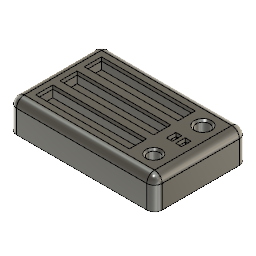
stand_ian270033 (Autodesk Fusion 360 design; units mm, degrees)
Autodesk Fusion 360 part; units mm, degrees
sketch "Sketch1" plane through (0, 0, 0) normal (0, 0, 1) x (1, 0, 0)
  line L0 (0, 0) -> (94.3, 0)
  line L1 (94.3, 0) -> (94.3, 60)
  line L2 (94.3, 60) -> (0, 60)
  line L3 (0, 60) -> (0, 0)
  dimension "d1" = 94.3
  dimension "d2" = 60
  constraint horizontal L0
  constraint vertical L1
  constraint horizontal L2
  constraint vertical L3
  constraint coincident L0.start L3.end
  measures "d1" distance of L0.start L0.end
  measures "d2" distance of L0 L2
extrude "Extrude1" add sketch "Sketch1" along normal blind 20
sketch "Sketch2" plane through (0, 0, 20) normal (0, 0, 1) x (-1, 0, 0)
  line L0 (0, -60) -> (0, 0)
  line L1 (0, 0) -> (-94.3, 0)
  line L2 (-94.3, 0) -> (-94.3, -60)
  line L3 (-94.3, -60) -> (0, -60)
  line L4 (-9.9, -50.1) -> (-68.1, -50.1)
  line L5 (-68.1, -50.1) -> (-68.1, -41.4)
  line L6 (-68.1, -41.4) -> (-9.9, -41.4)
  line L7 (-9.9, -41.4) -> (-9.9, -50.1)
  line L8 (-9.9, -34.35) -> (-68.1, -34.35)
  line L9 (-68.1, -25.65) -> (-9.9, -25.65)
  line L10 (-9.9, -25.65) -> (-9.9, -34.35)
  line L11 (-68.1, -34.35) -> (-68.1, -25.65)
  line L12 (0, 15.75) -> (-94.3, 15.75)
  line L13 (-9.9, -18.6) -> (-68.1, -18.6)
  line L14 (-68.1, -9.9) -> (-9.9, -9.9)
  line L15 (-9.9, -9.9) -> (-9.9, -18.6)
  line L16 (-68.1, -18.6) -> (-68.1, -9.9)
  line L17 (0, 31.5) -> (-94.3, 31.5)
  dimension "d5" = 8.7
  dimension "d6" = 58.2
  dimension "d7" = 9.9
  dimension "d8" = 9.9
  dimension "d11" = 0
  dimension "d12" = 31.5
  constraint horizontal L4
  constraint vertical L5
  constraint horizontal L6
  constraint vertical L7
  measures "d5" distance of L4.start L6.end
  measures "d6" distance of L4.start L4.end
  measures "d7" distance of L0 L7
  measures "d8" distance of L3 L4
extrude "Extrude2" cut sketch "Sketch2" against normal blind 6 contours L4 L5 L6 L7 | L8 L9 L10 L11 | L13 L14 L15 L16
sketch "Sketch3" plane through (0, 0, 20) normal (0, 0, 1) x (-1, 0, 0)
  line L0 (-9.9, -9.9) -> (-9.9, -18.6)
  line L1 (-9.9, -18.6) -> (-68.1, -18.6)
  line L2 (-68.1, -18.6) -> (-68.1, -9.9)
  line L3 (-68.1, -9.9) -> (-9.9, -9.9)
  line L4 (-9.9, -25.65) -> (-9.9, -34.35)
  line L5 (-9.9, -34.35) -> (-68.1, -34.35)
  line L6 (-68.1, -34.35) -> (-68.1, -25.65)
  line L7 (-68.1, -25.65) -> (-9.9, -25.65)
  line L8 (-68.1, -50.1) -> (-68.1, -41.4)
  line L9 (-68.1, -41.4) -> (-9.9, -41.4)
  line L10 (-9.9, -41.4) -> (-9.9, -50.1)
  line L11 (-9.9, -50.1) -> (-68.1, -50.1)
  line L12 (0, -60) -> (0, 0)
  line L13 (0, 0) -> (-94.3, 0)
  line L14 (-94.3, 0) -> (-94.3, -60)
  line L15 (-94.3, -60) -> (0, -60)
  circle A0 centre (-80, -13.85) radius 3.85
  circle A1 centre (-80, -45.65) radius 4.35
  line L16 (-77.752, -28.0633) -> (-76.352, -28.0633)
  line L17 (-76.352, -28.0633) -> (-76.352, -31.8633)
  line L18 (-76.352, -31.8633) -> (-77.752, -31.8633)
  line L19 (-77.752, -31.8633) -> (-77.752, -28.0633)
  line L20 (-77.752, -28.0633) -> (-76.352, -31.8633) construction
  line L21 (-76.352, -28.0633) -> (-77.752, -31.8633) construction
  line L22 (-83.752, -28.0633) -> (-82.352, -28.0633)
  line L23 (-82.352, -31.8633) -> (-83.752, -31.8633)
  line L24 (-82.352, -28.0633) -> (-83.752, -31.8633) construction
  line L25 (-82.352, -28.0633) -> (-82.352, -31.8633)
  line L26 (-83.752, -31.8633) -> (-83.752, -28.0633)
  line L27 (-83.752, -28.0633) -> (-82.352, -31.8633) construction
  point P0 (-77.052, -29.9633)
  point P1 (-83.052, -29.9633)
  dimension "d15" = 7.7
  dimension "d16" = 8.7
  dimension "d17" = 14.35
  dimension "d18" = 13.85
  dimension "d23" = 1.4
  dimension "d24" = 3.8
  dimension "d27" = -6
  dimension "d28" = 0
  constraint perpendicular L16 L17
  constraint parallel L16 L18
  constraint parallel L17 L19
  constraint horizontal L16
  constraint coincident L20 P0
  constraint coincident L21 P0
  measures "d15" diameter of A0
  measures "d16" diameter of A1
  measures "d17" distance of L15 A1.centre
  measures "d18" distance of L13 A0.centre
  measures "d23" distance of L17.end L18.end
  measures "d24" distance of L16.end L17.end
extrude "Extrude3" cut sketch "Sketch3" against normal blind 17 contours A0 | A1 | L16 L17 L18 L19 | L22 L23 L25 L26
fillet "Fillet1" radius 5 8 edges at (47.15, 0, 20) (94.3, 30, 20) (47.15, 60, 20) (0, 30, 20) (0, 0, 10) (94.3, 0, 10) (94.3, 60, 10) (0, 60, 10)
chamfer "Chamfer1" distance 1.2 angle 45 22 edges at (39, 9.9, 20) (9.9, 14.25, 20) (39, 18.6, 20) (68.1, 14.25, 20) (39, 25.65, 20) (68.1, 30, 20) (39, 34.35, 20) (9.9, 30, 20) (39, 41.4, 20) (9.9, 45.75, 20) (39, 50.1, 20) (68.1, 45.75, 20) (83.5895, 12.4578, 20) (84.0556, 44.077, 20) (77.052, 28.0633, 20) (77.752, 29.9633, 20) (77.052, 31.8633, 20) (76.352, 29.9633, 20) (83.752, 29.9633, 20) (83.052, 28.0633, 20) (83.052, 31.8633, 20) (82.352, 29.9633, 20)
chamfer "Chamfer2" distance 15 distance2 0.8 4 edges at (83.052, 31.8633, 3) (77.052, 31.8633, 3) (77.052, 28.0633, 3) (83.052, 28.0633, 3) measured on face at (82.8186, 31.8633, 8.2667) measured on face at (76.8186, 31.8633, 13.5333) measured on face at (77.2853, 28.0633, 13.5333) measured on face at (83.2853, 28.0633, 8.2667)
equation "d1 = 90 mm + ( ( 8.6 / 2 ) * 1 mm )"
equation "d17 = 10 mm + ( d16 / 2 )"
equation "d18 = 10 mm + ( d15 / 2 )"
